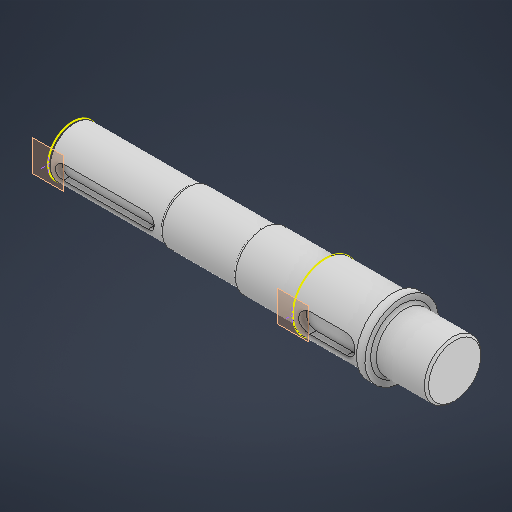
# Autodesk Inventor part: 低速轴
Saved by Autodesk Inventor 2026 (Build 300175000, 175)
## iProperties
Created: 2026-08-27
Part Number: 低速轴
Material: 常规
Document SubType Name: Modeling
Designer: 14170
Density: 1 g/cm^3
Appearance: 默认
Author: 14170
Autodesk Inventor part; units mm, degrees
ref_plane "YZ Plane" through (0, 0, 0) normal (1, 0, 0) x (0, 1, 0)
ref_plane "XZ Plane" through (0, 0, 0) normal (0, 1, 0) x (-1, 0, 0)
ref_plane "XY Plane" through (0, 0, 0) normal (0, 0, 1) x (1, 0, 0)
sketch "草图1" plane through (0, 0, 0) normal (0, 0, 1) x (1, 0, 0)
  line L0 (0, 0) -> (0, 17.5)
  line L1 (0, 17.5) -> (80, 17.5)
  line L2 (80, 17.5) -> (80, 18.5)
  line L3 (80, 18.5) -> (133, 18.5)
  line L4 (133, 18.5) -> (133, 20)
  line L5 (133, 20) -> (178.5, 20)
  line L6 (178.5, 20) -> (178.5, 23)
  line L7 (178.5, 23) -> (226.5, 23)
  line L8 (226.5, 23) -> (226.5, 26)
  line L9 (226.5, 26) -> (232.5, 26)
  line L10 (232.5, 26) -> (232.5, 20)
  line L11 (232.5, 20) -> (270, 20)
  line L12 (270, 20) -> (270, 0)
  line L13 (270, 0) -> (0, 0)
  dimension "d0" = 17.5
  dimension "d3" = 80
  dimension "d4" = 1
  dimension "d5" = 53
  dimension "d6" = 1.5
  dimension "d7" = 45.5
  dimension "d8" = 3
  dimension "d9" = 48
  dimension "d10" = 3
  dimension "d11" = 6
  dimension "d12" = 6
  dimension "d13" = 37.5
  constraints: 28 end point, 10 perpendicular, 2 point on line, 1 horizontal, 1 vertical
  measures "d0" distance of L0.start L0.end
  measures "d3" distance of L0.end L1.end
  measures "d4" distance of L1.end L2.end
  measures "d5" distance of L2.end L3.end
  measures "d6" distance of L3.end L4.end
  measures "d7" distance of L4.end L5.end
  measures "d8" distance of L5.end L6.end
  measures "d9" distance of L6.end L7.end
  measures "d10" distance of L7.end L8.end
  measures "d11" distance of L8.end L9.end
  measures "d12" distance of L9.end L10.end
  measures "d13" distance of L10.end L11.end
revolve "旋转1" add sketch "草图1" angle 360 about axis through (270, 0, 0) along (-1, 0, 0)
sketch "草图2" plane through (0, 0, 0) normal (-1, 0, 0) x (0, 0, 1)
  circle A0 centre (0, 0) radius 17.5 projected
  point P0 (17.5, 0)
  constraints: 1 horizontal alignment, 1 other
ref_plane "工作平面1" through (0, 0, 17.5) normal (0, 0, 1) x (1, 0, 0)
sketch "草图3" plane through (0, 0, 17.5) normal (0, 0, 1) x (1, 0, 0)
  line L0 (5, 0) -> (5, 0)
  line L1 (10, 5) -> (70, 5)
  line L2 (75, 0) -> (75, 0)
  line L3 (70, -5) -> (10, -5)
  line L4 (5, 0) -> (5, 0)
  arc A0 (10, 5) -> (5, 0) centre (10, 0) ccw
  arc A1 (5, 0) -> (10, -5) centre (10, 0) ccw
  arc A2 (70, -5) -> (75, 0) centre (70, 0) ccw
  arc A3 (75, 0) -> (70, 5) centre (70, 0) ccw
  point P0 (0, 0)
  point P1 (5, 5)
  point P2 (75, 5)
  point P3 (75, -5)
  point P4 (5, -5)
  point P5 (5, 0)
  point P6 (75, 0)
  dimension "d15" = 5
  dimension "d16" = 70
  dimension "d17" = 10
  dimension "d18" = 5
  constraints: 10 end point, 9 point on line, 8 point on circle, 8 tangent, 4 centre point, 4 perpendicular, 3 equal radius, 1 vertical
  measures "d15" distance of L0.start point (5, 5)
  measures "d16" distance of point (5, 5) point (75, 5)
  measures "d17" distance of point (75, 5) point (75, -5)
  measures "d18" radius of A0
extrude "拉伸1" cut sketch "草图3" against normal blind 5
sketch "草图4" plane through (178.5, 0, 0) normal (-1, 0, 0) x (0, 0, 1)
  circle A0 centre (0, 0) radius 23 projected
  point P0 (23, 0)
  constraints: 1 horizontal alignment, 1 other
ref_plane "工作平面2" through (178.5, 0, 23) normal (0, 0, 1) x (1, 0, 0)
sketch "草图5" plane through (178.5, 0, 23) normal (0, 0, 1) x (1, 0, 0)
  line L0 (4, 0) -> (4, 0)
  line L1 (11, 7) -> (37, 7)
  line L2 (44, 0) -> (44, 0)
  line L3 (37, -7) -> (11, -7)
  line L4 (4, 0) -> (4, 0)
  arc A0 (11, 7) -> (4, 0) centre (11, 0) ccw
  arc A1 (4, 0) -> (11, -7) centre (11, 0) ccw
  arc A2 (37, -7) -> (44, 0) centre (37, 0) ccw
  arc A3 (44, 0) -> (37, 7) centre (37, 0) ccw
  point P0 (-178.5, 0)
  point P1 (4, 7)
  point P2 (44, 7)
  point P3 (44, -7)
  point P4 (4, -7)
  point P5 (4, 0)
  point P6 (44, 0)
  dimension "d21" = 7
  dimension "d22" = 40
  dimension "d23" = 14
  dimension "d24" = 7
  constraints: 10 end point, 9 point on line, 8 point on circle, 8 tangent, 4 centre point, 4 perpendicular, 3 equal radius, 1 vertical
  measures "d21" distance of L0.start point (4, 7)
  measures "d22" distance of point (4, 7) point (44, 7)
  measures "d23" distance of point (44, 7) point (44, -7)
  measures "d24" radius of A0
extrude "拉伸2" cut sketch "草图5" against normal blind 5.5
chamfer "倒角1" distance 1.5 angle 45 2 edges at (0, -17.5, 0) (270, -20, 0)
fillet "圆角1" radius 2 5 edges at (80, -18.5, 0) (133, -20, 0) (178.5, -20, 0) (226.5, -23, 0) (232.5, -20, 0)
